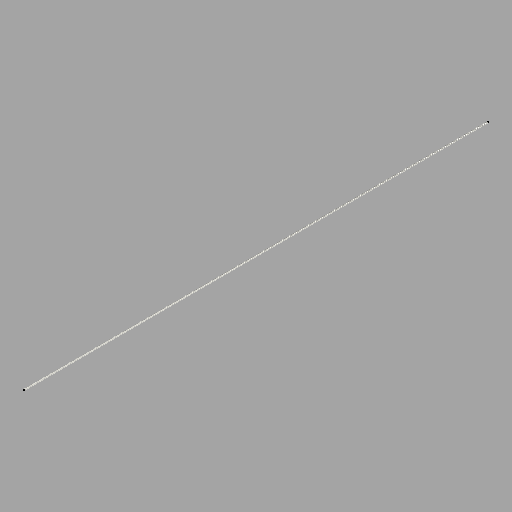
# Autodesk Inventor part: Cell_Ribbon_Start
Saved by Autodesk Inventor 2026.2 (Build 302298000, 298)
## iProperties
Created: 2026-11-08
Part Number: Cell_Ribbon_Start
Material: Generic
Document SubType Name: Modeling
Designer: Jacob
Density: 1 g/cm^3
Appearance: Default
Author: Jacob
Autodesk Inventor part; units mm, degrees
ref_plane "YZ Plane" through (0, 0, 0) normal (1, 0, 0) x (0, 1, 0)
ref_plane "XZ Plane" through (0, 0, 0) normal (0, 1, 0) x (-1, 0, 0)
sketch "Sketch1" plane through (0, 0, 0) normal (1, 0, 0) x (0, 1, 0)
  line L0 (0.315, -8) -> (0.315, 83.17)
  point P0 (0, 0)
  dimension "d0" = 0.315
  dimension "d1" = 8
  dimension "d2" = 83.17
  constraints: 2 end point, 1 vertical
  measures "d0" horizontal distance of point (0, 0) L0.start
  measures "d1" vertical distance of point (0, 0) L0.start
  measures "d2" vertical distance of point (0, 0) L0.end
ref_plane "Work Plane1" through (0, 0.315, -8) normal (0, 0, 1) x (1, 0, 0)
sketch "Sketch2" plane through (0, 0.315, -8) normal (0, 0, 1) x (1, 0, 0)
  circle A0 centre (0, 0) radius 0.135
  dimension "d3" = 0.27
  constraints: 1 centre point
  measures "d3" diameter of A0
sweep "Copper_Core_Sweep" add profiles "Sketch2" path "Sketch1"
sketch "Sketch3" plane through (0, 0.315, -8) normal (0, 0, 1) x (1, 0, 0)
  circle A0 centre (0, 0) radius 0.135
  circle A1 centre (0, 0) radius 0.15
  dimension "d6" = 0.27
  dimension "d7" = 0.3
  constraints: 2 centre point
  measures "d6" diameter of A0
  measures "d7" diameter of A1
sweep "SnPb_Coating_Sweep" add profiles "Sketch3" path "Sketch1" separate body contours A0 | A1
equation "\"d0\" = Cell_Thickness + 0.5 * Wire_OD"
equation "\"d1\" = Ribbon_Overhang"
equation "\"d2\" = Ribbon_Pad_Length"
equation "\"d3\" = Cu_Dia"
equation "\"d6\" = Cu_Dia"
equation "\"d7\" = Wire_OD"
equation "\"Cu_Dia\" = 0.27"
equation "\"Wire_OD\" = 0.3"
equation "\"Cell_Thickness\" = 0.165"
equation "\"Ribbon_Overhang\" = 8"
equation "\"Ribbon_Pad_Length\" = 83.17"
